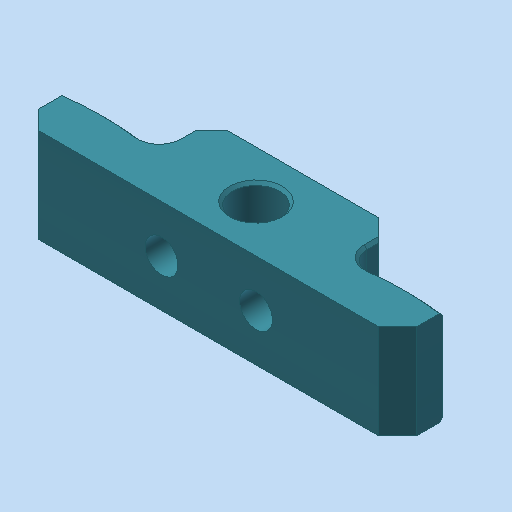
# Autodesk Inventor part: MM0861AN100_G01_116
Saved by Autodesk Inventor 2023.3 (Build 273359000, 359)
## iProperties
Created: 2018-10-30
Part Number: MM0861AN100_G01_116
Material: 1.2379 X155CrVMo 12-1
Document SubType Name: Modeling
Designer: Rose
Density: 7.85 g/cm^3
Appearance: Cyan
Description: =<RBPARTNOTITLE2>
Mass: 19.7849 g
Surface Area: 18.0364 cm^2
Volume: 2.52037 cm^3
RBMATERIAL: =<Material>
RBMATNO: =<Part Number>
RBPARTMADEOF: Präzi.4kt.10x43
RBPARTNOTITLE1: manufactured part
RBPARTNOTITLE2: Anfertigungsteil
MaxAbmaße: 0 x 0 x 0 (FM)
AnP_Material_aktuell: =<Material>
AnP_Kommentar_aktuell: =<Comments>
RBDRAWINGMISSINGSPEC: --
AnP_Kategorie: 1
AnP_Material: =<Material>
RBSURFACE2: HRC 60±2 DyLin beschichtet
Author: Rose
Keywords: =<RBPARTMADEOF>
Comments: =<RBSURFACE2>
Revision Number: 01
Autodesk Inventor part; units mm, degrees
ref_plane "YZ Plane" through (0, 0, 0) normal (1, 0, 0) x (0, 1, 0)
ref_plane "XZ Plane" through (0, 0, 0) normal (0, 1, 0) x (-1, 0, 0)
ref_plane "XY Plane" through (0, 0, 0) normal (0, 0, 1) x (1, 0, 0)
sketch "Skizze1" plane through (0, 0, 0) normal (0, 0, 1) x (1, 0, 0)
  line L0 (0, 12) -> (0, -37) projected
  line L1 (-28.0015, 0) -> (28.0015, 0) projected
  line L2 (-10, 5) -> (10, 5)
  line L3 (10, 5) -> (10, 1.749)
  line L4 (20, -0.2679) -> (20, -5)
  line L5 (20, -5) -> (-20, -5)
  line L6 (-20, -5) -> (-20, -0.2679)
  line L7 (-10, 1.749) -> (-10, 5)
  arc A0 (-12.25, -0.2353) -> (-20, -0.2679) centre (-16, -30) ccw
  arc A1 (20, -0.2679) -> (12.25, -0.2353) centre (16, -30) ccw
  arc A2 (-12.25, -0.2353) -> (-10, 1.749) centre (-12, 1.749) ccw
  arc A3 (10, 1.749) -> (12.25, -0.2353) centre (12, 1.749) ccw
  dimension "d0" = 20
  dimension "d1" = 5
  dimension "d4" = 30
  dimension "d5" = 4
  dimension "d6" = 4
  dimension "d7" = 16
  dimension "d8" = 16
  dimension "d12" = 5
  dimension "d13" = 2
  constraints: 12 end point, 8 point on circle, 6 tangent, 4 centre point, 4 perpendicular, 2 equal radius, 1 other
  measures "d0" distance between parallel lines of L3 L7
  measures "d1" distance between parallel lines of L1 L2
  measures "d4" radius of A0
  measures "d5" distance from line of L6 A0.centre
  measures "d6" distance from line of A1.centre L4
  measures "d7" distance from line of A0.centre L0
  measures "d8" distance from line of L0 A1.centre
  measures "d12" distance between parallel lines of L5 L1
  measures "d13" radius of A2
extrude "Extrusion1" add sketch "Skizze1" along normal mid plane 10 contours L2 L3 A3 L1 L0 | L0 L1 A2 L7 L2 | L1 A3 A1 L4 L5 L0 | L0 L5 L6 A0 A2 L1
sketch "Skizze2" plane through (0, 0, 5) normal (0, 0, 1) x (1, 0, 0)
  line L0 (0, 7) -> (0, -7) projected
  line L1 (-28, 0) -> (28, 0) projected
  point P0 (0, 0)
  constraints: 2 midpoint
hole "Bohrung1" at (0, 0, 5) direction (0, 0, -1) diameter 5 end through all
sketch "Skizze3" plane through (-10, 5, 5) normal (0, 1, 0) x (1, 0, 0)
  line L0 (10, 12) -> (10, -2) projected
  line L1 (38, 5) -> (-18, 5) projected
  point P0 (5, 5)
  point P1 (15, 5)
  dimension "d36" = 10
  constraints: 2 point on line, 1 symmetric about line
  measures "d36" distance of point (15, 5) point (5, 5)
hole "Bohrung2" at (-5, 5, 0) at (5, 5, 0) direction (0, -1, 0) diameter 3.5 end through all
chamfer "Fase1" distance 2 angle 45 4 edges at (-10, 5, 0) (10, 5, 0) (-20, -5, 0) (20, -5, 0)
chamfer "Fase2" distance 0.3 angle 45 14 edges at (-16.1261, -0.0003, -5) (-10.6771, 0.249, -5) (-10, 2.3745, -5) (-16.1261, -0.0003, 5) (-10.6771, 0.249, 5) (-10, 2.3745, 5) (16.1261, -0.0003, 5) (10.6771, 0.249, 5) (10, 2.3745, 5) (16.1261, -0.0003, -5) (10.6771, 0.249, -5) (10, 2.3745, -5) (0, 2.5, 5) (0, 2.5, -5)
